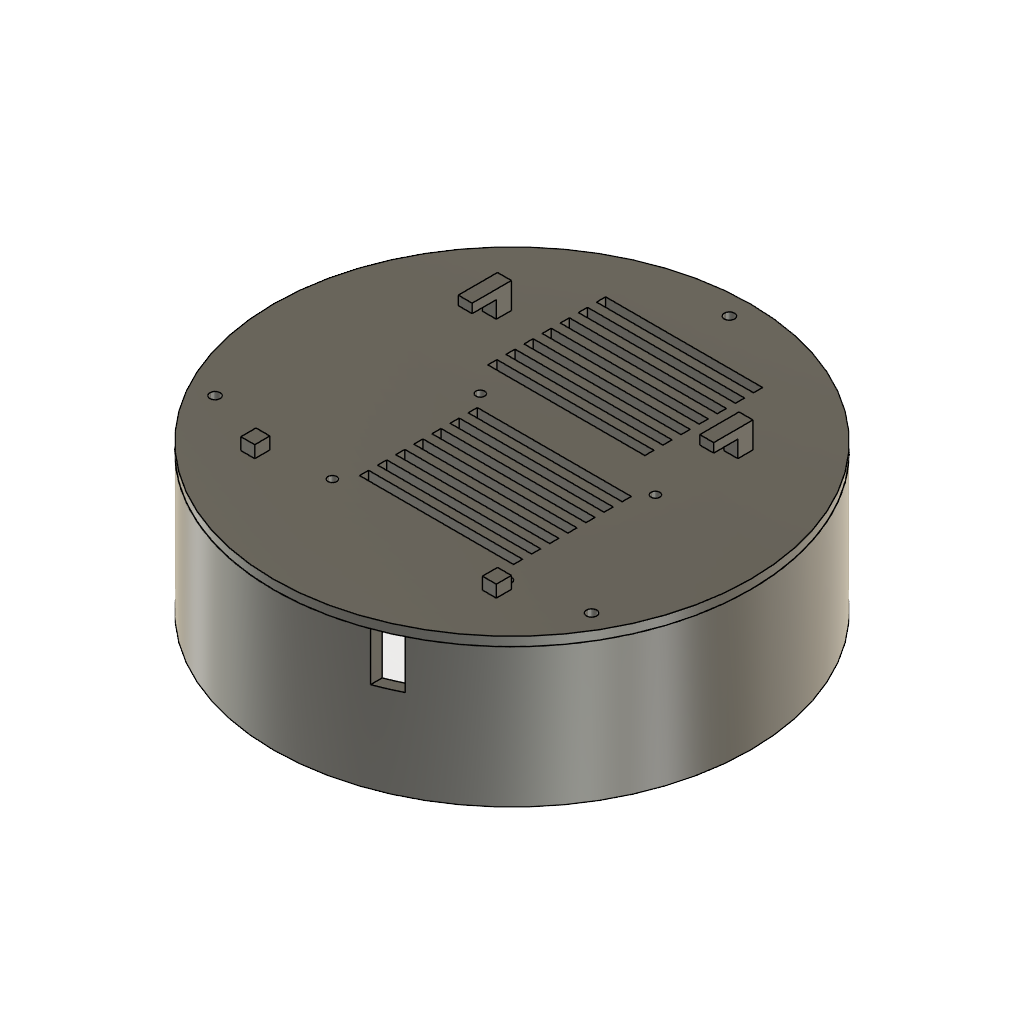
sky-radar-mount (Autodesk Fusion 360 design; units mm, degrees)
part number: 2026-11-16-22-37-20-287
Autodesk Fusion 360 part; units mm, degrees
sketch "Outer body" plane through (0, 0, 0) normal (0, 0, 1) x (1, 0, 0)
  circle A0 centre (0, 0) radius 79
extrude "Outer body (1)" add sketch "Outer body" along normal blind 46 makes body 1
sketch "Hollow inside" plane through (0, 0, 0) normal (0, 0, 1) x (1, 0, 0)
  circle A0 centre (0, 0) radius 75.4
extrude "Hollow inside (1)" cut sketch "Hollow inside" along normal blind 46 bodies 1
ref_plane "WorkPlane1" through (0, 0, 11.5) normal (0, 0, 1) x (1, 0, 0)
sketch "Display ledge" plane through (0, 0, 11.5) normal (0, 0, 1) x (1, 0, 0)
  circle A0 centre (0, 0) radius 75.9
  circle A1 centre (0, 0) radius 71
extrude "Display ledge (1)" add sketch "Display ledge" along normal blind 2.5 bodies 1
ref_plane "WorkPlane2" through (0, 0, 11.5) normal (0, 0, 1) x (1, 0, 0)
sketch "Display screw arms" plane through (0, 0, 11.5) normal (0, 0, 1) x (1, 0, 0)
  line L0 (35.881, 40.7437) -> (51.5922, 55.8507)
  line L1 (51.5922, 55.8507) -> (57.8302, 49.3632)
  line L2 (57.8302, 49.3632) -> (42.119, 34.2563)
  line L3 (42.119, 34.2563) -> (35.881, 40.7437)
  circle A0 centre (39, 37.5) radius 4.5
  line L4 (-39.2462, 34.3836) -> (-55.8094, 51.6369)
  line L5 (-55.8094, 51.6369) -> (-49.3169, 57.8697)
  line L6 (-49.3169, 57.8697) -> (-32.7538, 40.6164)
  line L7 (-32.7538, 40.6164) -> (-39.2462, 34.3836)
  circle A1 centre (-36, 37.5) radius 4.5
  line L8 (-32.7538, -40.6164) -> (-49.3169, -57.8697)
  line L9 (-49.3169, -57.8697) -> (-55.8094, -51.6369)
  line L10 (-55.8094, -51.6369) -> (-39.2462, -34.3836)
  line L11 (-39.2462, -34.3836) -> (-32.7538, -40.6164)
  circle A2 centre (-36, -37.5) radius 4.5
  line L12 (42.119, -34.2563) -> (57.8302, -49.3632)
  line L13 (57.8302, -49.3632) -> (51.5922, -55.8507)
  line L14 (51.5922, -55.8507) -> (35.881, -40.7437)
  line L15 (35.881, -40.7437) -> (42.119, -34.2563)
  circle A3 centre (39, -37.5) radius 4.5
extrude "Display screw arms (1)" add sketch "Display screw arms" along normal blind 3 bodies 1
ref_plane "WorkPlane3" through (0, 0, 11.5) normal (0, 0, 1) x (1, 0, 0)
sketch "M3 holes into display" plane through (0, 0, 11.5) normal (0, 0, 1) x (1, 0, 0)
  circle A0 centre (39, 37.5) radius 1.7
  circle A1 centre (-36, 37.5) radius 1.7
  circle A2 centre (-36, -37.5) radius 1.7
  circle A3 centre (39, -37.5) radius 1.7
extrude "M3 holes into display (1)" cut sketch "M3 holes into display" along normal blind 3 bodies 1
ref_plane "WorkPlane4" through (0, 0, 34) normal (0, 0, 1) x (1, 0, 0)
sketch "Lid screw bosses" plane through (0, 0, 34) normal (0, 0, 1) x (1, 0, 0)
  circle A0 centre (0, 72) radius 4.2
  circle A1 centre (-62.3538, -36) radius 4.2
  circle A2 centre (62.3538, -36) radius 4.2
extrude "Lid screw bosses (1)" add sketch "Lid screw bosses" along normal blind 12 bodies 1
ref_plane "WorkPlane5" through (0, 0, 37) normal (0, 0, 1) x (1, 0, 0)
sketch "Lid screw pilot holes" plane through (0, 0, 37) normal (0, 0, 1) x (1, 0, 0)
  circle A0 centre (0, 72) radius 1.3
  circle A1 centre (-62.3538, -36) radius 1.3
  circle A2 centre (62.3538, -36) radius 1.3
extrude "Lid screw pilot holes (1)" cut sketch "Lid screw pilot holes" along normal blind 9 bodies 1
ref_plane "WorkPlane6" through (0, 0, 30) normal (0, 0, 1) x (1, 0, 0)
sketch "USB-C power cable slot" plane through (0, 0, 30) normal (0, 0, 1) x (1, 0, 0)
  line L0 (27.3, -81) -> (35.3, -81)
  line L1 (35.3, -81) -> (35.3, -67.4)
  line L2 (35.3, -67.4) -> (27.3, -67.4)
  line L3 (27.3, -67.4) -> (27.3, -81)
extrude "USB-C power cable slot (1)" cut sketch "USB-C power cable slot" along normal blind 16 bodies 1
ref_plane "WorkPlane7" through (0, 0, 20) normal (0, 0, 1) x (1, 0, 0)
sketch "Top vents" plane through (0, 0, 20) normal (0, 0, 1) x (1, 0, 0)
  line L0 (-32, 69.4) -> (-28, 69.4)
  line L1 (-28, 69.4) -> (-28, 81)
  line L2 (-28, 81) -> (-32, 81)
  line L3 (-32, 81) -> (-32, 69.4)
  line L4 (-20, 69.4) -> (-16, 69.4)
  line L5 (-16, 69.4) -> (-16, 81)
  line L6 (-16, 81) -> (-20, 81)
  line L7 (-20, 81) -> (-20, 69.4)
  line L8 (-8, 69.4) -> (-4, 69.4)
  line L9 (-4, 69.4) -> (-4, 81)
  line L10 (-4, 81) -> (-8, 81)
  line L11 (-8, 81) -> (-8, 69.4)
  line L12 (4, 69.4) -> (8, 69.4)
  line L13 (8, 69.4) -> (8, 81)
  line L14 (8, 81) -> (4, 81)
  line L15 (4, 81) -> (4, 69.4)
  line L16 (16, 69.4) -> (20, 69.4)
  line L17 (20, 69.4) -> (20, 81)
  line L18 (20, 81) -> (16, 81)
  line L19 (16, 81) -> (16, 69.4)
  line L20 (28, 69.4) -> (32, 69.4)
  line L21 (32, 69.4) -> (32, 81)
  line L22 (32, 81) -> (28, 81)
  line L23 (28, 81) -> (28, 69.4)
extrude "Top vents (1)" cut sketch "Top vents" along normal blind 18 bodies 1
ref_plane "WorkPlane8" through (0, 0, 46) normal (0, 0, 1) x (1, 0, 0)
sketch "Lid plate" plane through (0, 0, 46) normal (0, 0, 1) x (1, 0, 0)
  circle A0 centre (0, 0) radius 79
extrude "Lid plate (1)" add sketch "Lid plate" along normal blind 3 separate body makes body 2
ref_plane "WorkPlane9" through (0, 0, 46) normal (0, 0, 1) x (1, 0, 0)
sketch "Lid screw holes (M3)" plane through (0, 0, 46) normal (0, 0, 1) x (1, 0, 0)
  circle A0 centre (0, 72) radius 1.7
  circle A1 centre (-62.3538, -36) radius 1.7
  circle A2 centre (62.3538, -36) radius 1.7
extrude "Lid screw holes (M3) (1)" cut sketch "Lid screw holes (M3)" along normal blind 3 bodies 2
ref_plane "WorkPlane10" through (0, 0, 46) normal (0, 0, 1) x (1, 0, 0)
sketch "Pi 5 M2.5 screw holes" plane through (0, 0, 46) normal (0, 0, 1) x (1, 0, 0)
  circle A0 centre (39, -40.5) radius 1.45
  circle A1 centre (-19, -40.5) radius 1.45
  circle A2 centre (39, 8.5) radius 1.45
  circle A3 centre (-19, 8.5) radius 1.45
extrude "Pi 5 M2.5 screw holes (1)" cut sketch "Pi 5 M2.5 screw holes" along normal blind 3 bodies 2
ref_plane "WorkPlane11" through (0, 0, 46) normal (0, 0, 1) x (1, 0, 0)
sketch "Fan intake slots (over the cooler)" plane through (0, 0, 46) normal (0, 0, 1) x (1, 0, 0)
  line L0 (-15.5, -35) -> (35.5, -35)
  line L1 (35.5, -35) -> (35.5, -32)
  line L2 (35.5, -32) -> (-15.5, -32)
  line L3 (-15.5, -32) -> (-15.5, -35)
  line L4 (-15.5, -29) -> (35.5, -29)
  line L5 (35.5, -29) -> (35.5, -26)
  line L6 (35.5, -26) -> (-15.5, -26)
  line L7 (-15.5, -26) -> (-15.5, -29)
  line L8 (-15.5, -23) -> (35.5, -23)
  line L9 (35.5, -23) -> (35.5, -20)
  line L10 (35.5, -20) -> (-15.5, -20)
  line L11 (-15.5, -20) -> (-15.5, -23)
  line L12 (-15.5, -17) -> (35.5, -17)
  line L13 (35.5, -17) -> (35.5, -14)
  line L14 (35.5, -14) -> (-15.5, -14)
  line L15 (-15.5, -14) -> (-15.5, -17)
  line L16 (-15.5, -11) -> (35.5, -11)
  line L17 (35.5, -11) -> (35.5, -8)
  line L18 (35.5, -8) -> (-15.5, -8)
  line L19 (-15.5, -8) -> (-15.5, -11)
  line L20 (-15.5, -5) -> (35.5, -5)
  line L21 (35.5, -5) -> (35.5, -2)
  line L22 (35.5, -2) -> (-15.5, -2)
  line L23 (-15.5, -2) -> (-15.5, -5)
  line L24 (-15.5, 1) -> (35.5, 1)
  line L25 (35.5, 1) -> (35.5, 4)
  line L26 (35.5, 4) -> (-15.5, 4)
  line L27 (-15.5, 4) -> (-15.5, 1)
extrude "Fan intake slots (over the cooler) (1)" cut sketch "Fan intake slots (over the cooler)" along normal blind 3 bodies 2
ref_plane "WorkPlane12" through (0, 0, 46) normal (0, 0, 1) x (1, 0, 0)
sketch "Upper vent slots" plane through (0, 0, 46) normal (0, 0, 1) x (1, 0, 0)
  line L0 (-26, 18) -> (26, 18)
  line L1 (26, 18) -> (26, 21)
  line L2 (26, 21) -> (-26, 21)
  line L3 (-26, 21) -> (-26, 18)
  line L4 (-26, 24) -> (26, 24)
  line L5 (26, 24) -> (26, 27)
  line L6 (26, 27) -> (-26, 27)
  line L7 (-26, 27) -> (-26, 24)
  line L8 (-26, 30) -> (26, 30)
  line L9 (26, 30) -> (26, 33)
  line L10 (26, 33) -> (-26, 33)
  line L11 (-26, 33) -> (-26, 30)
  line L12 (-26, 36) -> (26, 36)
  line L13 (26, 36) -> (26, 39)
  line L14 (26, 39) -> (-26, 39)
  line L15 (-26, 39) -> (-26, 36)
  line L16 (-26, 42) -> (26, 42)
  line L17 (26, 42) -> (26, 45)
  line L18 (26, 45) -> (-26, 45)
  line L19 (-26, 45) -> (-26, 42)
  line L20 (-26, 48) -> (26, 48)
  line L21 (26, 48) -> (26, 51)
  line L22 (26, 51) -> (-26, 51)
  line L23 (-26, 51) -> (-26, 48)
  line L24 (-26, 54) -> (26, 54)
  line L25 (26, 54) -> (26, 57)
  line L26 (26, 57) -> (-26, 57)
  line L27 (-26, 57) -> (-26, 54)
extrude "Upper vent slots (1)" cut sketch "Upper vent slots" along normal blind 3 bodies 2
ref_plane "WorkPlane13" through (0, 0, 49) normal (0, 0, 1) x (1, 0, 0)
sketch "Skadis hook stem" plane through (0, 0, 49) normal (0, 0, 1) x (1, 0, 0)
  line L0 (-42.3, 32.5) -> (-37.7, 32.5)
  line L1 (-37.7, 32.5) -> (-37.7, 37.5)
  line L2 (-37.7, 37.5) -> (-42.3, 37.5)
  line L3 (-42.3, 37.5) -> (-42.3, 32.5)
extrude "Skadis hook stem (1)" add sketch "Skadis hook stem" along normal blind 5.6 bodies 2
ref_plane "WorkPlane14" through (0, 0, 54.6) normal (0, 0, 1) x (1, 0, 0)
sketch "Skadis hook lip" plane through (0, 0, 54.6) normal (0, 0, 1) x (1, 0, 0)
  line L0 (-42.3, 24.5) -> (-37.7, 24.5)
  line L1 (-37.7, 24.5) -> (-37.7, 37.5)
  line L2 (-37.7, 37.5) -> (-42.3, 37.5)
  line L3 (-42.3, 37.5) -> (-42.3, 24.5)
extrude "Skadis hook lip (1)" add sketch "Skadis hook lip" along normal blind 3 bodies 2
ref_plane "WorkPlane15" through (0, 0, 49) normal (0, 0, 1) x (1, 0, 0)
sketch "Skadis hook stem (1)" plane through (0, 0, 49) normal (0, 0, 1) x (1, 0, 0)
  line L0 (37.7, 32.5) -> (42.3, 32.5)
  line L1 (42.3, 32.5) -> (42.3, 37.5)
  line L2 (42.3, 37.5) -> (37.7, 37.5)
  line L3 (37.7, 37.5) -> (37.7, 32.5)
extrude "Skadis hook stem (2)" add sketch "Skadis hook stem (1)" along normal blind 5.6 bodies 2
ref_plane "WorkPlane16" through (0, 0, 54.6) normal (0, 0, 1) x (1, 0, 0)
sketch "Skadis hook lip (1)" plane through (0, 0, 54.6) normal (0, 0, 1) x (1, 0, 0)
  line L0 (37.7, 24.5) -> (42.3, 24.5)
  line L1 (42.3, 24.5) -> (42.3, 37.5)
  line L2 (42.3, 37.5) -> (37.7, 37.5)
  line L3 (37.7, 37.5) -> (37.7, 24.5)
extrude "Skadis hook lip (2)" add sketch "Skadis hook lip (1)" along normal blind 3 bodies 2
ref_plane "WorkPlane17" through (0, 0, 49) normal (0, 0, 1) x (1, 0, 0)
sketch "Skadis anti-tilt peg" plane through (0, 0, 49) normal (0, 0, 1) x (1, 0, 0)
  line L0 (-42.3, -47.5) -> (-37.7, -47.5)
  line L1 (-37.7, -47.5) -> (-37.7, -42.5)
  line L2 (-37.7, -42.5) -> (-42.3, -42.5)
  line L3 (-42.3, -42.5) -> (-42.3, -47.5)
extrude "Skadis anti-tilt peg (1)" add sketch "Skadis anti-tilt peg" along normal blind 4 bodies 2
ref_plane "WorkPlane18" through (0, 0, 49) normal (0, 0, 1) x (1, 0, 0)
sketch "Skadis anti-tilt peg (1)" plane through (0, 0, 49) normal (0, 0, 1) x (1, 0, 0)
  line L0 (37.7, -47.5) -> (42.3, -47.5)
  line L1 (42.3, -47.5) -> (42.3, -42.5)
  line L2 (42.3, -42.5) -> (37.7, -42.5)
  line L3 (37.7, -42.5) -> (37.7, -47.5)
extrude "Skadis anti-tilt peg (2)" add sketch "Skadis anti-tilt peg (1)" along normal blind 4 bodies 2
sketch "Display" plane through (0, 0, 0) normal (0, 0, 1) x (1, 0, 0)
  circle A0 centre (0, 0) radius 75
extrude "Display (1)" add sketch "Display" along normal blind 11.5 separate body makes body 3
ref_plane "WorkPlane19" through (0, 0, 11.5) normal (0, 0, 1) x (1, 0, 0)
sketch "Display board" plane through (0, 0, 11.5) normal (0, 0, 1) x (1, 0, 0)
  line L0 (-45.4, -30) -> (41, -30)
  line L1 (41, -30) -> (41, 28)
  line L2 (41, 28) -> (-45.4, 28)
  line L3 (-45.4, 28) -> (-45.4, -30)
extrude "Display board (1)" add sketch "Display board" along normal blind 6.6 separate body makes body 4
ref_plane "WorkPlane20" through (0, 0, 24.4) normal (0, 0, 1) x (1, 0, 0)
sketch "REF Pi 5 board" plane through (0, 0, 24.4) normal (0, 0, 1) x (1, 0, 0)
  line L0 (-42.5, -44) -> (42.5, -44)
  line L1 (42.5, -44) -> (42.5, 12)
  line L2 (42.5, 12) -> (-42.5, 12)
  line L3 (-42.5, 12) -> (-42.5, -44)
extrude "REF Pi 5 board (1)" add sketch "REF Pi 5 board" along normal blind 1.6 separate body makes body 5
ref_plane "WorkPlane21" through (0, 0, 26) normal (0, 0, 1) x (1, 0, 0)
sketch "REF Active cooler" plane through (0, 0, 26) normal (0, 0, 1) x (1, 0, 0)
  line L0 (-18.5, -38) -> (38.5, -38)
  line L1 (38.5, -38) -> (38.5, 5)
  line L2 (38.5, 5) -> (-18.5, 5)
  line L3 (-18.5, 5) -> (-18.5, -38)
extrude "REF Active cooler (1)" add sketch "REF Active cooler" along normal blind 14 separate body makes body 6
ref_plane "WorkPlane22" through (0, 0, 26) normal (0, 0, 1) x (1, 0, 0)
sketch "REF USB + Ethernet" plane through (0, 0, 26) normal (0, 0, 1) x (1, 0, 0)
  line L0 (-42.5, -42) -> (-21.5, -42)
  line L1 (-21.5, -42) -> (-21.5, 11)
  line L2 (-21.5, 11) -> (-42.5, 11)
  line L3 (-42.5, 11) -> (-42.5, -42)
extrude "REF USB + Ethernet (1)" add sketch "REF USB + Ethernet" along normal blind 16 separate body makes body 7
ref_plane "WorkPlane23" through (0, 0, 26) normal (0, 0, 1) x (1, 0, 0)
sketch "REF Pi USB-C" plane through (0, 0, 26) normal (0, 0, 1) x (1, 0, 0)
  line L0 (26.8, -45) -> (35.8, -45)
  line L1 (35.8, -45) -> (35.8, -37)
  line L2 (35.8, -37) -> (26.8, -37)
  line L3 (26.8, -37) -> (26.8, -45)
extrude "REF Pi USB-C (1)" add sketch "REF Pi USB-C" along normal blind 3.5 separate body makes body 8
ref_plane "WorkPlane24" through (0, 0, 26) normal (0, 0, 1) x (1, 0, 0)
sketch "REF M2.5 standoffs" plane through (0, 0, 26) normal (0, 0, 1) x (1, 0, 0)
  circle A0 centre (39, -40.5) radius 2.5
  circle A1 centre (-19, -40.5) radius 2.5
  circle A2 centre (39, 8.5) radius 2.5
  circle A3 centre (-19, 8.5) radius 2.5
extrude "REF M2.5 standoffs (1)" add sketch "REF M2.5 standoffs" along normal blind 20 separate body makes body 9 at (41.4969, 8.3754, 39.3333) makes body 10 at (-16.5031, -40.6246, 39.3333) makes body 11 at (41.4969, -40.6246, 39.3333) makes body 12 at (-16.5031, 8.3754, 39.3333)
named bodies: "Shell", "Lid", "Display", "Display board", "REF Pi 5 board", "REF Active cooler", "REF USB + Ethernet", "REF Pi USB-C", "REF standoffs 20mm", "REF standoffs 20mm (1)", "REF standoffs 20mm (2)", "REF standoffs 20mm (3)"
